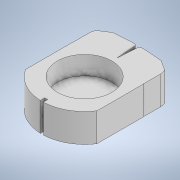
# Autodesk Inventor part: baza_statuie_magnet_8mm_cu tesitura si pe spate
Saved by Autodesk Inventor 2022.6 (Build 266554000, 554)
## iProperties
Created: 2025-03-27
Part Number: baza_statuie_magnet_8mm_cu tesitura si pe spate
Material: Generic
Document SubType Name: Modeling
Designer: Dragos Macovei
Density: 1 g/cm^3
Appearance: Default
Author: Dragos Macovei
Autodesk Inventor part; units mm, degrees
ref_plane "YZ Plane" through (0, 0, 0) normal (1, 0, 0) x (0, 1, 0)
ref_plane "XZ Plane" through (0, 0, 0) normal (0, 1, 0) x (-1, 0, 0)
ref_plane "XY Plane" through (0, 0, 0) normal (0, 0, 1) x (1, 0, 0)
sketch "Sketch1" plane through (0, 0, 0) normal (0, 1, 0) x (-1, 0, 0)
  line L0 (0.4, 21.1669) -> (0.4, 19.9499)
  line L1 (0.4, 19.9499) -> (-0.4, 19.9499)
  line L2 (-0.4, 19.9499) -> (-0.4, 21.1669)
  circle A0 centre (0, 9.1738) radius 11.9998
  line L3 (10.0403, 15.7457) -> (10.0403, 2.581)
  line L4 (-10.0403, 2.581) -> (-10.0403, 15.7457)
  line L5 (-10, 2.5607) -> (-10, -2)
  circle A1 centre (-5.9992, -1.9998) radius 4.0008
  line L6 (-9.6402, -3.6581) -> (-6.7935, -5.4743)
  line L7 (-6.7935, -5.4743) -> (-2.2975, -5.828)
  line L8 (-2.2975, -5.828) -> (-0.8597, -5.828)
  line L9 (-0.4299, -5.4645) -> (0, 0)
  line L10 (-0.8597, -5.828) -> (-0.4299, -5.4645)
  line L11 (0.4299, -5.4645) -> (0, 0)
  line L12 (0.4299, -5.4645) -> (0.8597, -5.828)
  line L13 (0.8597, -5.828) -> (2.2975, -5.828)
  line L14 (2.2975, -5.828) -> (6.7935, -5.4743)
  line L15 (6.7935, -5.4743) -> (9.6402, -3.6581)
  circle A2 centre (5.9996, -1.9999) radius 4.0004
  line L16 (10, -2) -> (10, 2.5607)
  point P0 (63.8478, 4.6277)
  point P1 (-10.0403, 15.7456)
  point P2 (-10.0403, 2.6019)
  point P3 (-0.2221, -2.824)
  point P4 (0.2221, -2.824)
  point P5 (10.0403, 2.602)
  point P6 (10.0403, 15.7455)
  point P7 (-10, -1.9931)
  point P8 (-8.7217, 0.9319)
  point P9 (-10, 2.5408)
  point P10 (10, -1.9915)
  point P11 (10, 2.5409)
  point P12 (-2.0514, -2.6494)
  point P13 (-4.3913, -5.6633)
  constraints: 34 end point, 2 centre point, 3 other
extrude "Extrusion1" add sketch "Sketch1" along normal blind 8 contours A0 L3 A2 L11 L9 A1 L4 L2 L1 L0 | L16 A2 A0 | A2 L15 L14 A0 | A0 A2 | A0 A1 L5 | A2 L14 L13 L12 L11 A0 | A1 A0 | A0 A1 L7 L6 | A0 L9 L10 L8 L7 A1
sketch "Sketch2" plane through (0, 8, 0) normal (0, 1, 0) x (1, 0, 0)
  line L0 (0.4, -19.9499) -> (0.4, -21.1669) projected
  arc A0 (0.4, -21.1669) -> (10.0403, -15.7456) centre (0, -9.1738) ccw projected
  line L1 (10.0403, -15.7456) -> (10.0403, -2.6019) projected
  arc A1 (10.0403, -2.6019) -> (10, -2.5408) centre (0, -9.1738) ccw projected
  line L2 (10, -2.5408) -> (10, 1.9931) projected
  arc A2 (10, 1.9931) -> (9.6402, 3.6581) centre (5.9992, 1.9998) ccw projected
  line L3 (9.6402, 3.6581) -> (6.7935, 5.4743) projected
  line L4 (6.7935, 5.4743) -> (2.2975, 5.828) projected
  line L5 (2.2975, 5.828) -> (0.8597, 5.828) projected
  line L6 (0.8597, 5.828) -> (0.4299, 5.4645) projected
  line L7 (0.4299, 5.4645) -> (0, 0) projected
  line L8 (0, 0) -> (-0.4299, 5.4645) projected
  line L9 (-0.4299, 5.4645) -> (-0.8597, 5.828) projected
  line L10 (-0.8597, 5.828) -> (-2.2975, 5.828) projected
  line L11 (-2.2975, 5.828) -> (-6.7935, 5.4743) projected
  line L12 (-6.7935, 5.4743) -> (-9.6402, 3.6581) projected
  arc A3 (-9.6402, 3.6581) -> (-10, 1.9915) centre (-5.9996, 1.9999) ccw projected
  line L13 (-10, 1.9915) -> (-10, -2.5409) projected
  arc A4 (-10, -2.5409) -> (-10.0403, -2.602) centre (0, -9.1738) ccw projected
  line L14 (-10.0403, -2.602) -> (-10.0403, -15.7455) projected
  arc A5 (-10.0403, -15.7455) -> (-0.4, -21.1669) centre (0, -9.1738) ccw projected
  line L15 (-0.4, -21.1669) -> (-0.4, -19.9499) projected
  line L16 (-0.4, -19.9499) -> (0.4, -19.9499) projected
  circle A6 centre (0, -9.1738) radius 7.65
  dimension "d2" = 15.3
  constraints: 1 centre point, 1 coincident
  measures "d2" diameter of A6
extrude "Extrusion2" cut sketch "Sketch2" against normal blind 5.2 contours A6
body "Solid1"
